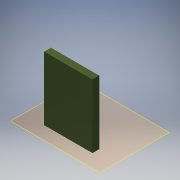
# Autodesk Inventor part: soporte vertical
Saved by Autodesk Inventor 2017 (Build 210142000, 142)
## iProperties
Part Number: soporte vertical
Material: Genérico
Document SubType Name: Modeling
Designer: HP Pav
Density: 1 g/cm^3
Appearance: Valor por defecto
Author: HP Pav
Autodesk Inventor part; units mm, degrees
ref_plane "YZ Plane" through (0, 0, 0) normal (1, 0, 0) x (0, 1, 0)
ref_plane "XZ Plane" through (0, 0, 0) normal (0, 1, 0) x (-1, 0, 0)
ref_plane "XY Plane" through (0, 0, 0) normal (0, 0, 1) x (1, 0, 0)
ref_plane "Plano de trabajo1" through (0, 0, 0) normal (0, 0, 1) x (1, 0, 0)
sketch "Boceto1" plane through (0, 0, 0) normal (0, 0, 1) x (1, 0, 0)
  line L0 (74, -66.45) -> (-75, -66.45)
  line L1 (-75, -66.45) -> (-75, -45.45)
  line L2 (-75, -45.45) -> (74, -45.45)
  line L3 (74, -45.45) -> (74, -66.45)
  line L4 (-125, -97.25) -> (125, -97.25) projected
  line L5 (125, -97.25) -> (125, 97.25) projected
  line L6 (-125, 97.25) -> (-125, -97.25) projected
  point P0 (0, 0)
  dimension "d0" = 149
  dimension "d1" = 21
  dimension "d2" = 30.8
  dimension "d3" = 50
  constraints: 8 end point, 2 parallel, 1 horizontal, 1 perpendicular
  measures "d0" distance of L0.start L0.end
  measures "d1" distance of L2.end L0.start
  measures "d2" distance between parallel lines of L0 L4
  measures "d3" distance between parallel lines of L6 L1
extrude "Extrusión1" add sketch "Boceto1" along normal blind 196.5
